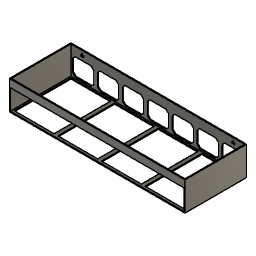
Large_Holder_PRINT (Autodesk Fusion 360 design; units mm, degrees)
Autodesk Fusion 360 part; units mm, degrees
sketch "Bottom" plane through (0, 0, 0) normal (0, 0, 1) x (1, 0, 0)
  line L0 (0, 0) -> (232.6, 0)
  line L1 (232.6, 0) -> (232.6, 81.6)
  line L2 (232.6, 81.6) -> (0, 81.6)
  line L3 (0, 81.6) -> (0, 0)
  line L4 (1.2, 80.4) -> (231.4, 80.4)
  line L5 (231.4, 80.4) -> (231.4, 1.2)
  line L6 (231.4, 1.2) -> (1.2, 1.2)
  line L7 (1.2, 1.2) -> (1.2, 80.4)
  line L8 (3.2, 3.2) -> (3.2, 78.4)
  line L9 (33.4, 80.4) -> (34.2, 80.4)
  line L10 (34.2, 1.2) -> (33.4, 1.2)
  line L11 (66.4, 80.4) -> (67.2, 80.4)
  line L12 (67.2, 1.2) -> (66.4, 1.2)
  line L13 (99.4, 80.4) -> (100.2, 80.4)
  line L14 (100.2, 1.2032) -> (99.4, 1.2032)
  line L15 (132.4, 80.4) -> (133.2, 80.4)
  line L16 (133.2, 1.2) -> (132.4, 1.2)
  line L17 (165.4, 80.4) -> (166.2, 80.4)
  line L18 (166.2, 1.2) -> (165.4, 1.2)
  line L19 (198.4, 80.4) -> (199.2, 80.4)
  line L20 (199.2, 1.2) -> (198.4, 1.2)
  line L21 (229.4, 78.4) -> (229.4, 3.2)
  line L22 (231.4, 80.4) -> (232.2, 80.4)
  line L23 (232.2, 1.2) -> (231.4, 1.2)
  line L24 (3.2, 78.4) -> (113.9, 78.4)
  line L25 (113.9, 3.2) -> (3.2, 3.2)
  line L26 (229.4, 78.4) -> (118.7, 78.4)
  line L27 (229.4, 3.2) -> (113.8, 3.2)
  line L28 (118.7, 78.4) -> (113.9, 78.4)
  line L29 (113.9, 3.2) -> (113.8, 3.2)
  line L30 (56, 80.4) -> (56, 1.2)
  line L31 (61, 80.4) -> (61, 1.2)
  line L32 (113.8, 80.4) -> (113.8, 1.2)
  line L33 (118.8, 1.2) -> (118.8, 80.4)
  line L34 (171.6, 3.2) -> (171.6, 80.4)
  line L35 (176.6, 80.4) -> (176.6, 1.2)
  line L36 (171.6, 3.2) -> (171.6, 1.2)
  dimension "d1" = 1.2
  dimension "d2" = 1.2
  dimension "d3" = 1.2
  dimension "d4" = 1.2
  dimension "d5" = 2
  dimension "d8" = 81.6
  dimension "d52" = 2
  dimension "d191" = 2
  dimension "d192" = 2
  dimension "d194" = 2
  dimension "d195" = 2
  dimension "d306" = 5
  dimension "d307" = 5
  dimension "d308" = 52.8
  dimension "d311" = 52.8
  dimension "d312" = 52.8
  dimension "d313" = 5
  dimension "d318" = 52.8
  constraint horizontal L0
  constraint vertical L1
  constraint horizontal L2
  constraint vertical L3
  constraint coincident L0.start L3.end
  constraint horizontal L4
  constraint vertical L5
  constraint horizontal L6
  constraint vertical L7
  constraint vertical L8
  constraint horizontal L9
  constraint coincident L6 L10.start
  constraint coincident L4 L9.start
  constraint horizontal L11
  constraint horizontal L12
  constraint coincident L4 L11.start
  constraint horizontal L13
  constraint horizontal L14
  constraint coincident L4 L13.start
  constraint horizontal L15
  constraint horizontal L16
  constraint coincident L4 L15.start
  constraint horizontal L17
  constraint horizontal L18
  constraint coincident L4 L17.start
  constraint horizontal L19
  constraint horizontal L20
  constraint coincident L4 L19.start
  constraint vertical L21
  constraint horizontal L22
  constraint horizontal L23
  constraint coincident L4 L5.start
  constraint perpendicular L8 L25
  constraint coincident L4 L30.start
  constraint coincident L6 L30.end
  constraint perpendicular L6 L30
  constraint coincident L4 L31.start
  constraint coincident L6 L31.end
  constraint perpendicular L0 L31
  constraint coincident L4 L32.start
  constraint coincident L6 L32.end
  constraint perpendicular L6 L32
  constraint coincident L6 L33.start
  constraint perpendicular L4 L33
  constraint coincident L4 L33.end
  constraint midpoint L27 L34.start
  constraint coincident L4 L34.end
  constraint perpendicular L4 L34
  constraint coincident L4 L35.start
  constraint coincident L6 L35.end
  constraint perpendicular L6 L35
  constraint coincident L6 L36.end
  constraint perpendicular L6 L36
  measures "d1" distance of L3 L7
  measures "d2" distance of L2 L4
  measures "d3" distance of L0 L6
  measures "d4" distance of L1 L5
  measures "d5" distance of L7 L8
  measures "d8" distance of L0.start L2.end
  measures "d52" distance of L5 L21
  measures "d191" distance of L4 L24
  measures "d192" distance of L6 L25
  measures "d194" distance of L6 L27
  measures "d195" distance of L4 L26
  measures "d306" distance of L30 L31
  measures "d307" distance of L32 L33
  measures "d308" distance of L8 L30
  measures "d311" distance of L31 L32
  measures "d312" distance of L33 L34
  measures "d313" distance of L34 L35
  measures "d318" distance of L21 L35
extrude "Extrude2" add sketch "Bottom" along normal blind 38.2
sketch "Front" plane through (0, 0, 0) normal (0, -1, 0) x (1, 0, 0)
  line L0 (0, 0) -> (232.6, 0)
  line L1 (232.6, 0) -> (232.6, 38.2)
  line L2 (232.6, 38.2) -> (0, 38.2)
  line L3 (0, 38.2) -> (0, 0)
  line L4 (1.2, 28.2) -> (33.4, 28.2)
  line L5 (33.4, 1.2) -> (1.2, 1.2)
  line L6 (1.2, 1.2) -> (1.2, 28.2)
  line L7 (1.2, 0) -> (1.2, 38.2)
  line L8 (231.4, 28.2) -> (231.4, 1.2)
  line L9 (33.4, 28.2) -> (231.4, 28.2)
  line L10 (231.4, 1.2) -> (33.4, 1.2)
  dimension "d80" = 27
  dimension "d83" = 10
  dimension "d91" = 27
  dimension "d319" = 1.2
  constraint horizontal L4
  constraint horizontal L5
  constraint vertical L6
  constraint collinear L6 L7
  constraint vertical L8
  constraint perpendicular L8 L9
  measures "d80" distance of L4.start L5.end
  measures "d83" distance of L2 L4
  measures "d91" distance of L8.start L8.end
  measures "d319" distance of L1 L8
sketch "Back" plane through (0, 80.4, 0) normal (0, -1, 0) x (1, 0, 0)
  line L0 (231.4, 0) -> (231.4, 38.2)
  line L1 (231.4, 38.2) -> (1.2, 38.2)
  line L2 (1.2, 38.2) -> (1.2, 0)
  line L3 (3.2, 6.7355) -> (6.7355, 3.2)
  line L4 (6.7355, 3.2) -> (27.8645, 3.2)
  line L5 (6.7355, 26.2711) -> (3.2, 22.7355)
  line L6 (3.2, 22.7355) -> (3.2, 6.7355)
  line L7 (27.8645, 26.271) -> (27.8645, 26.2711)
  line L8 (31.4, 6.7355) -> (31.4, 22.7355)
  line L9 (31.4, 22.7355) -> (27.8645, 26.2711)
  line L10 (1.2, 0) -> (231.4, 0)
  line L11 (27.8645, 3.2) -> (31.4, 6.7355)
  line L12 (27.8645, 26.271) -> (6.7355, 26.2711)
  line L13 (60.8645, 26.2728) -> (39.7355, 26.2729)
  line L14 (39.7355, 26.2729) -> (36.2, 22.7374)
  line L15 (36.2, 22.7374) -> (36.2, 6.7374)
  line L16 (36.2, 6.7374) -> (39.7355, 3.2019)
  line L17 (39.7355, 3.2019) -> (60.8645, 3.2019)
  line L18 (60.8645, 3.2019) -> (64.4, 6.7374)
  line L19 (64.4, 6.7374) -> (64.4, 22.7374)
  line L20 (93.8645, 26.271) -> (72.7355, 26.2711)
  line L21 (72.7355, 26.2711) -> (69.2, 22.7355)
  line L22 (69.2, 22.7355) -> (69.2, 6.7355)
  line L23 (69.2, 6.7355) -> (72.7355, 3.2)
  line L24 (72.7355, 3.2) -> (93.8645, 3.2)
  line L25 (93.8645, 3.2) -> (97.4, 6.7355)
  line L26 (97.4, 6.7355) -> (97.4, 22.7355)
  line L27 (126.8645, 26.271) -> (105.7355, 26.2711)
  line L28 (105.7355, 26.2711) -> (102.2, 22.7355)
  line L29 (102.2, 22.7355) -> (102.2, 6.7355)
  line L30 (102.2, 6.7355) -> (105.7355, 3.2)
  line L31 (105.7355, 3.2) -> (126.8645, 3.2)
  line L32 (126.8645, 3.2) -> (130.4, 6.7355)
  line L33 (130.4, 6.7355) -> (130.4, 22.7355)
  line L34 (159.8645, 26.271) -> (138.7355, 26.2711)
  line L35 (138.7355, 26.2711) -> (135.2, 22.7355)
  line L36 (135.2, 22.7355) -> (135.2, 6.7355)
  line L37 (135.2, 6.7355) -> (138.7355, 3.2)
  line L38 (138.7355, 3.2) -> (159.8645, 3.2)
  line L39 (159.8645, 3.2) -> (163.4, 6.7355)
  line L40 (163.4, 6.7355) -> (163.4, 22.7355)
  line L41 (192.8645, 26.271) -> (171.7355, 26.2711)
  line L42 (171.7355, 26.2711) -> (168.2, 22.7355)
  line L43 (168.2, 22.7355) -> (168.2, 6.7355)
  line L44 (168.2, 6.7355) -> (171.7355, 3.2)
  line L45 (171.7355, 3.2) -> (192.8645, 3.2)
  line L46 (192.8645, 3.2) -> (196.4, 6.7355)
  line L47 (196.4, 6.7355) -> (196.4, 22.7355)
  line L48 (225.8645, 26.271) -> (204.7355, 26.2711)
  line L49 (204.7355, 26.2711) -> (201.2, 22.7355)
  line L50 (201.2, 22.7355) -> (201.2, 6.7355)
  line L51 (201.2, 6.7355) -> (204.7355, 3.2)
  line L52 (204.7355, 3.2) -> (225.8645, 3.2)
  line L53 (225.8645, 3.2) -> (229.4, 6.7355)
  line L54 (229.4, 6.7355) -> (229.4, 22.7355)
  line L55 (232.6, 0) -> (232.6, 38.2)
  line L56 (0, 0) -> (0, 38.2)
  line L57 (60.8645, 26.2728) -> (64.4, 22.7374)
  line L58 (97.4, 22.7355) -> (93.8645, 26.271)
  line L59 (130.4, 22.7355) -> (126.8645, 26.271)
  line L60 (163.4, 22.7355) -> (159.8645, 26.271)
  line L61 (196.4, 22.7355) -> (192.8645, 26.271)
  line L62 (229.4, 22.7355) -> (225.8645, 26.271)
  dimension "d97" = 5
  dimension "d99" = 5
  dimension "d179" = 5
  dimension "d201" = 28.2
  dimension "d202" = 5
  dimension "d206" = 3.2
  dimension "d208" = 135
  dimension "d209" = 135
  dimension "d210" = 135
  dimension "d212" = 16
  dimension "d213" = 21.1289
  dimension "d215" = 135
  dimension "d216" = 135
  dimension "d219" = 5
  dimension "d220" = 5
  dimension "d222" = 28.2
  dimension "d223" = 5
  dimension "d224" = 16
  dimension "d225" = 135
  dimension "d226" = 135
  dimension "d228" = 16
  dimension "d229" = 21.1289
  dimension "d230" = 135
  dimension "d232" = 5
  dimension "d233" = 5
  dimension "d235" = 28.2
  dimension "d236" = 5
  dimension "d238" = 135
  dimension "d239" = 135
  dimension "d241" = 16
  dimension "d242" = 21.1289
  dimension "d243" = 135
  dimension "d245" = 5
  dimension "d246" = 5
  dimension "d248" = 28.2
  dimension "d249" = 5
  dimension "d250" = 16
  dimension "d251" = 135
  dimension "d252" = 135
  dimension "d254" = 16
  dimension "d255" = 21.1289
  dimension "d256" = 135
  dimension "d258" = 5
  dimension "d259" = 5
  dimension "d261" = 28.2
  dimension "d262" = 5
  dimension "d263" = 16
  dimension "d264" = 135
  dimension "d265" = 135
  dimension "d267" = 16
  dimension "d268" = 21.1289
  dimension "d269" = 135
  dimension "d271" = 5
  dimension "d272" = 5
  dimension "d274" = 28.2
  dimension "d275" = 5
  dimension "d276" = 16
  dimension "d277" = 135
  dimension "d278" = 135
  dimension "d280" = 16
  dimension "d281" = 21.1289
  dimension "d282" = 135
  dimension "d284" = 5
  dimension "d285" = 5
  dimension "d287" = 28.2
  dimension "d288" = 5
  dimension "d289" = 16
  dimension "d290" = 135
  dimension "d291" = 135
  dimension "d293" = 16
  dimension "d294" = 21.1289
  dimension "d295" = 135
  dimension "d297" = 4.8
  dimension "d298" = 4.8
  dimension "d299" = 4.8
  dimension "d300" = 4.8
  dimension "d301" = 4.8
  dimension "d302" = 4.8
  dimension "d304" = 3.2
  dimension "d305" = 4.9999
  dimension "d320" = 3.2019
  dimension "d321" = 3.2
  dimension "d323" = 3.2
  constraint parallel L2 L6
  constraint vertical L8
  constraint vertical L19
  constraint vertical L26
  constraint vertical L33
  constraint vertical L40
  constraint vertical L47
  constraint vertical L54
  measures "d97" distance of L5.start L5.end
  measures "d99" distance of L3.start L3.end
  measures "d179" distance of L8.end L7.end
  measures "d201" distance of L6 L8
  measures "d202" distance of L4.end L8.start
  measures "d206" distance of L4 L10
  measures "d208" angle of L3 L4
  measures "d209" angle of L8 L11
  measures "d210" angle of L8 L9
  measures "d212" distance of L3.start L5.end
  measures "d213" horizontal distance of L7.start L5.start
  measures "d215" angle of L5 L12
  measures "d216" angle of L9 L12
  measures "d219" distance of L14.end L13.end
  measures "d220" distance of L15.end L16.end
  measures "d222" distance of L15 L19
  measures "d223" distance of L18.end L17.end
  measures "d224" distance of L18.end L19.end
  measures "d225" angle of L16 L17
  measures "d226" angle of L18 L19
  measures "d228" distance of L15.end L14.end
  measures "d229" horizontal distance of L13.start L13.end
  measures "d230" angle of L13 L14
  measures "d232" distance of L21.end L20.end
  measures "d233" distance of L22.end L23.end
  measures "d235" distance of L22 L26
  measures "d236" distance of L25.end L24.end
  measures "d238" angle of L23 L24
  measures "d239" angle of L25 L26
  measures "d241" distance of L22.end L21.end
  measures "d242" horizontal distance of L20.start L20.end
  measures "d243" angle of L20 L21
  measures "d245" distance of L28.end L27.end
  measures "d246" distance of L29.end L30.end
  measures "d248" distance of L29 L33
  measures "d249" distance of L32.end L31.end
  measures "d250" distance of L32.end L33.end
  measures "d251" angle of L30 L31
  measures "d252" angle of L32 L33
  measures "d254" distance of L29.end L28.end
  measures "d255" horizontal distance of L27.start L27.end
  measures "d256" angle of L27 L28
  measures "d258" distance of L35.end L34.end
  measures "d259" distance of L36.end L37.end
  measures "d261" distance of L36 L40
  measures "d262" distance of L39.end L38.end
  measures "d263" distance of L39.end L40.end
  measures "d264" angle of L37 L38
  measures "d265" angle of L39 L40
  measures "d267" distance of L36.end L35.end
  measures "d268" horizontal distance of L34.start L34.end
  measures "d269" angle of L34 L35
  measures "d271" distance of L42.end L41.end
  measures "d272" distance of L43.end L44.end
  measures "d274" distance of L43 L47
  measures "d275" distance of L46.end L45.end
  measures "d276" distance of L46.end L47.end
  measures "d277" angle of L44 L45
  measures "d278" angle of L46 L47
  measures "d280" distance of L43.end L42.end
  measures "d281" horizontal distance of L41.start L41.end
  measures "d282" angle of L41 L42
  measures "d284" distance of L49.end L48.end
  measures "d285" distance of L50.end L51.end
  measures "d287" distance of L50 L54
  measures "d288" distance of L53.end L52.end
  measures "d289" distance of L53.end L54.end
  measures "d290" angle of L51 L52
  measures "d291" angle of L53 L54
  measures "d293" distance of L50.end L49.end
  measures "d294" horizontal distance of L48.start L48.end
  measures "d295" angle of L48 L49
  measures "d297" distance of L8 L15
  measures "d298" distance of L19 L22
  measures "d299" distance of L26 L29
  measures "d300" distance of L33 L36
  measures "d301" distance of L40 L43
  measures "d302" distance of L47 L50
  measures "d304" distance of L6 L56
  measures "d305" distance of L40.end L34.start
  measures "d320" distance of L10 L17
  measures "d321" distance of L10 L24
  measures "d323" distance of L10 L31
sketch "Mounting" plane through (0, 80.4, 0) normal (0, -1, 0) x (1, 0, 0)
  line L0 (231.4, 0) -> (231.4, 38.2)
  line L1 (231.4, 38.2) -> (1.2, 38.2)
  line L2 (1.2, 38.2) -> (1.2, 0)
  circle A0 centre (216.3, 32.2) radius 2
  circle A1 centre (16.3, 32.2) radius 2
  line L3 (1.2, 0) -> (231.4, 0)
  dimension "d165" = 4
  dimension "d166" = 4
  dimension "d167" = 15.1
  dimension "d168" = 6
  dimension "d169" = 15.1
  dimension "d170" = 6
  measures "d165" diameter of A0
  measures "d166" diameter of A1
  measures "d167" distance of L2 A1.centre
  measures "d168" distance of L1 A1.centre
  measures "d169" distance of L0 A0.centre
  measures "d170" distance of L1 A0.centre
extrude "Extrude9" cut sketch "Front" against normal up to surface (1.2 mm away) contours L4 L5 L6 L7 L8 L9 L10
extrude "Extrude10" cut sketch "Back" against normal blind 1.2 contours L3 L4 L5 L6 L8 L9 L11 L12 | L13 L14 L15 L16 L17 L18 L19 L57 | L20 L21 L22 L23 L24 L25 L26 L58 | L27 L28 L29 L30 L31 L32 L33 L59 | L34 L35 L36 L37 L38 L39 L40 L60 | L41 L42 L43 L44 L45 L46 L47 L61 | L48 L49 L50 L51 L52 L53 L54 L62
extrude "Extrude11" cut sketch "Mounting" against normal blind 1.2 contours A0 | A1
extrude "Extrude12" add sketch "Bottom" along normal up to surface (1.2 mm away) contours L4 L6 L7 L8 L9 L10 L24 L25 L30 | L4 L24 L30 L31 | L4 L11 L13 L24 L31 L32 | L6 L25 L30 L31 | L6 L12 L25 L31 L32 | L4 L24 L26 L28 L32 L33 | L6 L25 L27 L29 L32 L33 | L4 L15 L17 L26 L33 L34 | L6 L16 L18 L27 L33 L36 | L4 L26 L34 L35 | L6 L27 L35 L36 | L4 L5 L6 L19 L20 L21 L26 L27 L35
extrude "Extrude13" add sketch "Bottom" along normal up to surface (1.2 mm away) contours L4 L6 L7 L8 L9 L10 L24 L25 L30 | L4 L24 L30 L31 | L4 L11 L13 L24 L31 L32 | L6 L25 L30 L31 | L6 L12 L25 L31 L32 | L4 L24 L26 L28 L32 L33 | L6 L25 L27 L29 L32 L33 | L4 L15 L17 L26 L33 L34 | L6 L16 L18 L27 L33 L36 | L4 L26 L34 L35 | L6 L27 L35 L36 | L4 L5 L6 L19 L20 L21 L26 L27 L35
extrude "Extrude15" add sketch "Bottom" along normal blind 1.2 contours L24 L25 L30 L31 | L24 L25 L26 L27 L28 L29 L32 L33 | L26 L27 L34 L35
